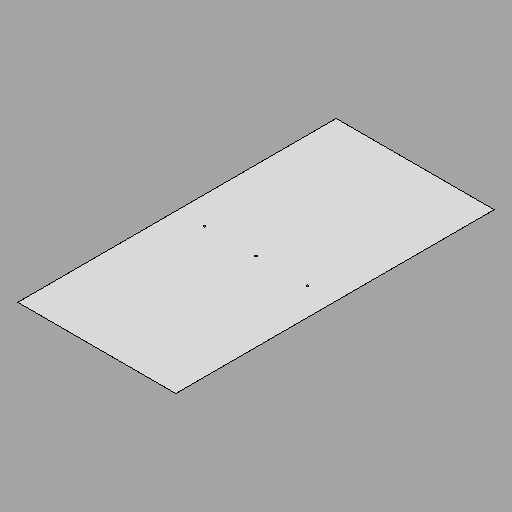
# Autodesk Inventor part: Backsheet
Saved by Autodesk Inventor 2026.2 (Build 302298000, 298)
## iProperties
Created: 2026-11-08
Part Number: Backsheet
Material: Generic
Document SubType Name: Modeling
Designer: Jacob
Density: 1 g/cm^3
Appearance: Smooth - White
Backsheet_Thickness: 0.305 mm
Author: Jacob
Autodesk Inventor part; units mm, degrees
ref_plane "YZ Plane" through (0, 0, 0) normal (1, 0, 0) x (0, 1, 0)
ref_plane "XZ Plane" through (0, 0, 0) normal (0, 1, 0) x (-1, 0, 0)
ref_plane "XY Plane" through (0, 0, 0) normal (0, 0, 1) x (1, 0, 0)
sketch "Sketch1" plane through (0, 0, 0) normal (0, 1, 0) x (-1, 0, 0)
  line L0 (564, -1136.5) -> (-564, -1136.5)
  line L1 (-564, -1136.5) -> (-564, 1136.5)
  line L2 (-564, 1136.5) -> (564, 1136.5)
  line L3 (564, 1136.5) -> (564, -1136.5)
  line L4 (373.6, -6) -> (361.6, -6)
  line L5 (361.6, -6) -> (361.6, 6)
  line L6 (361.6, 6) -> (373.6, 6)
  line L7 (373.6, 6) -> (373.6, -6)
  line L8 (6, -6) -> (-6, -6)
  line L9 (-6, -6) -> (-6, 6)
  line L10 (-6, 6) -> (6, 6)
  line L11 (6, 6) -> (6, -6)
  line L12 (-361.6, -6) -> (-373.6, -6)
  line L13 (-373.6, -6) -> (-373.6, 6)
  line L14 (-373.6, 6) -> (-361.6, 6)
  line L15 (-361.6, 6) -> (-361.6, -6)
  constraints: 32 end point
extrude "Extrusion1" add sketch "Sketch1" along normal blind 0.305
equation "\"d0\" = Backsheet_Thickness"
equation "\"Backsheet_Thickness\" = 0.305"
body "Solid1"
